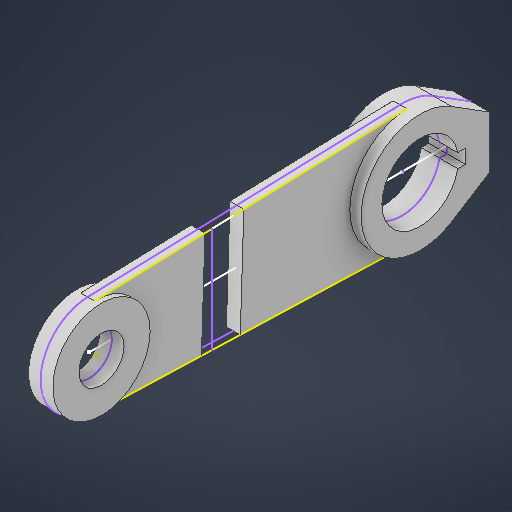
# Autodesk Inventor part: Peça5
Saved by Autodesk Inventor 2026.2 (Build 302298000, 298)
## iProperties
Created: 2026-08-07
Part Number: Peça5
Material: Genérico
Document SubType Name: Modeling
Designer: IFSP
Density: 1 g/cm^3
Appearance: Padrão
Author: IFSP
Autodesk Inventor part; units mm, degrees
ref_plane "YZ Plane" through (0, 0, 0) normal (1, 0, 0) x (0, 1, 0)
ref_plane "XZ Plane" through (0, 0, 0) normal (0, 1, 0) x (-1, 0, 0)
ref_plane "XY Plane" through (0, 0, 0) normal (0, 0, 1) x (1, 0, 0)
sketch "Esboço1" plane through (0, 0, 0) normal (0, 0, 1) x (1, 0, 0)
  circle A0 centre (0, 0) radius 13
  circle A1 centre (0, 0) radius 28.0188
  line L0 (0, 0) -> (180, 0)
  arc A2 (201.6333, 4) -> (201.6333, -4) centre (180, 0) ccw
  arc A3 (198.1089, 28.7761) -> (198.1089, -28.7761) centre (180, 0) ccw
  line L1 (180, 0) -> (220, 0)
  line L2 (220, 0) -> (220, 15)
  line L3 (220, 15) -> (220, -15)
  line L4 (220, 15) -> (198.1089, 28.7761)
  line L5 (220, -15) -> (198.1089, -28.7761)
  line L6 (158, 0) -> (206, 0)
  line L7 (206, 0) -> (206, 4)
  line L8 (206, 4) -> (201.6333, 4)
  line L9 (206, 0) -> (206, -4)
  line L10 (206, -4) -> (201.6333, -4)
  line L11 (178.8702, 33.9812) -> (-0.931, 28.0033)
  line L12 (-0.931, -28.0033) -> (178.8702, -33.9812)
  constraints: 26 end point, 9 point on circle, 6 tangent, 4 centre point, 4 coincident, 4 point on line, 3 perpendicular, 2 horizontal, 1 vertical
extrude "Extrusão1" add sketch "Esboço1" along normal mid plane 8 contours A1 | A1 L11 A3 L0 | L0 A3 L12 A1 | A3 L4 L2 L1 L7 L8 A2 L0 | L0 A2 L10 L9 L1 L3 L5 A3
extrude "Extrusão2" add sketch "Esboço1" along normal mid plane 14 contours A1
extrude "Extrusão3" add sketch "Esboço1" along normal mid plane 21 contours A3 L4 L2 L1 L7 L8 A2 L0 | L0 A2 L10 L9 L1 L3 L5 A3
sketch "Esboço2" plane through (0, 0, 4) normal (0, 0, 1) x (1, 0, 0)
  line L0 (-0.931, 28.0033) -> (178.8702, 33.9812) projected
  line L1 (66.6871, 30.2514) -> (66.6871, -30.2514)
  line L2 (178.8702, -33.9812) -> (-0.931, -28.0033) projected
  line L3 (66.6871, -30.2514) -> (66.6871, 30.2514)
  line L4 (66.6871, 30.2514) -> (66.6871, 30.2514)
  line L5 (66.6871, 30.2514) -> (66.6871, 30.2514)
  line L6 (66.6871, 30.2514) -> (66.6871, 30.2514)
  line L7 (66.6871, -30.2514) -> (66.6871, -30.2514)
  line L8 (66.6871, 30.2514) -> (66.6871, 30.2514)
  line L9 (66.6871, 30.2514) -> (66.6871, -30.2514)
  line L10 (66.6871, 30.2514) -> (78.6215, 30.6482)
  point P0 (0, 0)
  constraints: 18 end point, 5 collinear, 3 point on line, 2 vertical, 1 perpendicular
sketch "Esboço3" plane through (0, 0, 4) normal (0, 0, 1) x (1, 0, 0)
  line L0 (-0.931, 28.0033) -> (178.8702, 33.9812) projected
  line L1 (66.9378, 30.2598) -> (75.1559, 30.533)
  line L2 (76.075, 30.5636) -> (76.075, -30.5636)
  line L3 (178.8702, -33.9812) -> (-0.931, -28.0033) projected
  line L4 (63.8952, -35.6066) -> (82.7481, -36.2334)
  line L5 (82.7481, -36.2334) -> (85.339, 41.6947)
  line L6 (85.339, 41.6947) -> (63.0032, 42.4373)
  line L7 (63.0032, 42.4373) -> (60.4123, -35.4908)
  line L8 (60.4123, -35.4908) -> (63.8952, -35.6066)
  point P0 (0, 0)
  constraints: 14 end point, 5 point on line, 4 perpendicular, 1 vertical
extrude "Extrusão4" cut sketch "Esboço3" against normal blind 21
